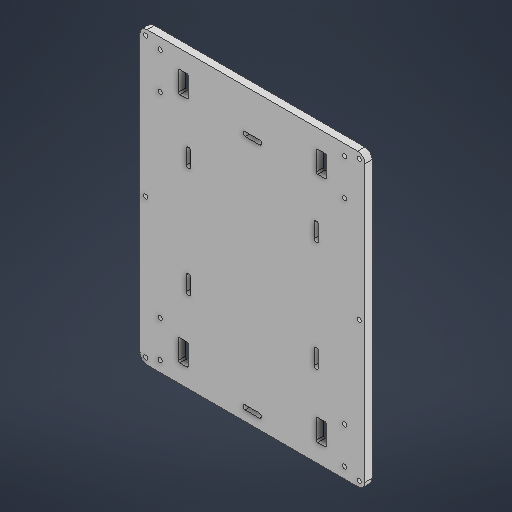
# Autodesk Inventor part: Part3
Saved by Autodesk Inventor 2026.3 (Build 303398000, 398)
## iProperties
Created: 2026-07-17
Part Number: Part3
Material: Generic
Document SubType Name: Modeling
Designer: nose
Density: 1 g/cm^3
Appearance: Default
motor_x_offset: 14.000 mm
motor_y_offset: 20.000 mm
base_width: 155.000 mm
base_length: 200.000 mm
standoff_offset: 4.000 mm
base_fillet: 5.000 mm
Author: nose
Autodesk Inventor part; units mm, degrees
ref_plane "YZ Plane" through (0, 0, 0) normal (1, 0, 0) x (0, 1, 0)
ref_plane "XZ Plane" through (0, 0, 0) normal (0, 1, 0) x (-1, 0, 0)
ref_plane "XY Plane" through (0, 0, 0) normal (0, 0, 1) x (1, 0, 0)
sketch "Sketch1" plane through (0, 0, 0) normal (0, 0, 1) x (1, 0, 0)
  line L0 (72.5, -100) -> (-72.5, -100)
  line L1 (-77.5, -95) -> (-77.5, 95)
  line L2 (-72.5, 100) -> (72.5, 100)
  line L3 (77.5, 95) -> (77.5, -95)
  line L4 (77.5, -100) -> (-77.5, 100) construction
  line L5 (-77.5, -100) -> (77.5, 100) construction
  arc A0 (-72.5, 100) -> (-77.5, 95) centre (-72.5, 95) ccw
  arc A1 (77.5, 95) -> (72.5, 100) centre (72.5, 95) ccw
  arc A2 (72.5, -100) -> (77.5, -95) centre (72.5, -95) ccw
  arc A3 (-77.5, -95) -> (-72.5, -100) centre (-72.5, -95) ccw
  point P0 (0, 0)
  dimension "d0" = 155
  dimension "d1" = 200
  dimension "d26" = 5
  constraints: 12 end point, 8 point on circle, 8 point on line, 8 tangent, 4 centre point, 3 equal radius, 2 midpoint, 2 parallel, 1 horizontal, 1 perpendicular
  measures "d0" distance of L4.end L5.end
  measures "d1" distance of L5.start L4.end
  measures "d26" radius of A0
extrude "base" add sketch "Sketch1" along normal blind 5
sketch "Sketch2" plane through (0, 0, 5) normal (0, 0, 1) x (1, 0, 0)
  circle A0 centre (-63.5, 92.6) radius 1.5
  circle A1 centre (-63.5, 67.4) radius 1.5
  line L0 (-90.3018, 80) -> (-26.5899, 80) construction
  line L1 (-63.5, 59.4965) -> (-63.5, 108.4491) construction
  line L2 (-45, 72.5) -> (-50, 72.5)
  line L3 (-51, 73.5) -> (-51, 86.5)
  line L4 (-50, 87.5) -> (-45, 87.5)
  line L5 (-44, 86.5) -> (-44, 73.5)
  line L6 (-44, 72.5) -> (-51, 87.5) construction
  line L7 (-51, 72.5) -> (-44, 87.5) construction
  arc A2 (-50, 87.5) -> (-51, 86.5) centre (-50, 86.5) ccw
  arc A3 (-44, 86.5) -> (-45, 87.5) centre (-45, 86.5) ccw
  arc A4 (-45, 72.5) -> (-44, 73.5) centre (-45, 73.5) ccw
  arc A5 (-51, 73.5) -> (-50, 72.5) centre (-50, 73.5) ccw
  line L8 (0, -165.9432) -> (0, 165.9432) construction
  line L9 (-120.5021, 0) -> (120.5021, 0) construction
  circle A6 centre (63.5, 92.6) radius 1.5
  circle A7 centre (63.5, 67.4) radius 1.5
  line L10 (45, 72.5) -> (50, 72.5)
  line L11 (51, 73.5) -> (51, 86.5)
  line L12 (50, 87.5) -> (45, 87.5)
  line L13 (44, 86.5) -> (44, 73.5)
  line L14 (44, 72.5) -> (51, 87.5) construction
  line L15 (51, 72.5) -> (44, 87.5) construction
  arc A8 (51, 86.5) -> (50, 87.5) centre (50, 86.5) ccw
  arc A9 (45, 87.5) -> (44, 86.5) centre (45, 86.5) ccw
  arc A10 (44, 73.5) -> (45, 72.5) centre (45, 73.5) ccw
  arc A11 (50, 72.5) -> (51, 73.5) centre (50, 73.5) ccw
  circle A12 centre (-63.5, -92.6) radius 1.5
  circle A13 centre (-63.5, -67.4) radius 1.5
  line L16 (-45, -72.5) -> (-50, -72.5)
  line L17 (-51, -73.5) -> (-51, -86.5)
  line L18 (-50, -87.5) -> (-45, -87.5)
  line L19 (-44, -86.5) -> (-44, -73.5)
  line L20 (-44, -72.5) -> (-51, -87.5) construction
  line L21 (-51, -72.5) -> (-44, -87.5) construction
  arc A14 (-51, -86.5) -> (-50, -87.5) centre (-50, -86.5) ccw
  arc A15 (-45, -87.5) -> (-44, -86.5) centre (-45, -86.5) ccw
  arc A16 (-44, -73.5) -> (-45, -72.5) centre (-45, -73.5) ccw
  arc A17 (-50, -72.5) -> (-51, -73.5) centre (-50, -73.5) ccw
  arc A18 (51, -73.5) -> (50, -72.5) centre (50, -73.5) ccw
  line L22 (45, -72.5) -> (50, -72.5)
  line L23 (51, -73.5) -> (51, -86.5)
  arc A19 (50, -87.5) -> (51, -86.5) centre (50, -86.5) ccw
  line L24 (44, -86.5) -> (44, -73.5)
  line L25 (50, -87.5) -> (45, -87.5)
  line L26 (51, -72.5) -> (44, -87.5) construction
  line L27 (44, -72.5) -> (51, -87.5) construction
  arc A20 (44, -86.5) -> (45, -87.5) centre (45, -86.5) ccw
  arc A21 (45, -72.5) -> (44, -73.5) centre (45, -73.5) ccw
  circle A22 centre (63.5, -67.4) radius 1.5
  circle A23 centre (63.5, -92.6) radius 1.5
  point P0 (0, 0)
  point P1 (-47.5, 80)
  point P2 (-47.5, 72.5)
  point P3 (63.5, 59.4965)
  point P4 (47.5, 80)
  point P5 (47.5, 72.5)
  point P6 (-26.5899, -80)
  point P7 (-47.5, -80)
  point P8 (-47.5, -72.5)
  point P9 (47.5, -72.5)
  point P10 (47.5, -80)
  dimension "d4" = 3
  dimension "d5" = 3
  dimension "d6" = 25.2
  dimension "d7" = 12.6
  dimension "d8" = 63.5
  dimension "d9" = 80
  dimension "d10" = 7
  dimension "d11" = 15
  dimension "d12" = 12.5
  dimension "d13" = 1
  dimension "d14" = 1
  dimension "d15" = 1
  dimension "d16" = 1
  constraints: 62 symmetric about line, 56 end point, 35 point on line, 32 point on circle, 24 centre point, 8 tangent, 5 midpoint, 3 horizontal, 2 parallel, 2 vertical, 1 perpendicular, 18 other
  measures "d4" diameter of A0
  measures "d5" diameter of A1
  measures "d6" distance of A1.centre A0.centre
  measures "d7" distance from line of L0 A0.centre
  measures "d8" distance from line of point (0, 0) L1
  measures "d9" distance from line of point (0, 0) L0
  measures "d10" distance of L6.end L7.end
  measures "d11" distance from line of point (-47.5, 72.5) L4
  measures "d12" distance from line of L3 A0.centre
  measures "d13" radius of A2
  measures "d14" radius of A3
  measures "d15" radius of A4
  measures "d16" radius of A5
extrude "motor_mount" cut sketch "Sketch2" against normal through all
sketch "Sketch4" plane through (0, 0, 5) normal (0, 0, 1) x (1, 0, 0)
  circle A0 centre (-73.5, 96) radius 1.5
  line L0 (0, -163.8328) -> (0, 163.8328) construction
  line L1 (-154.6878, 0) -> (154.6878, 0) construction
  circle A1 centre (73.5, 96) radius 1.5
  circle A2 centre (-73.5, -96) radius 1.5
  circle A3 centre (73.5, -96) radius 1.5
  circle A4 centre (-73.5, 0) radius 1.5
  line L2 (-77.5, 95) -> (-77.5, -95) projected
  circle A5 centre (73.5, 0) radius 1.5
  point P0 (0, 0)
  dimension "d21" = 3
  dimension "d22" = 73.5
  dimension "d23" = 96
  dimension "d46" = 3
  dimension "d47" = 4
  constraints: 6 centre point, 4 end point, 4 symmetric about line, 2 midpoint, 1 horizontal, 1 point on line, 1 vertical, 4 other
  measures "d21" diameter of A0
  measures "d22" horizontal distance of point (0, 0) A0.centre
  measures "d23" vertical distance of point (0, 0) A0.centre
  measures "d46" diameter of A4
  measures "d47" distance from line of L2 A4.centre
extrude "standoff_mount" cut sketch "Sketch4" against normal through all
sketch "Sketch5" plane through (0, 0, 5) normal (0, 0, 1) x (1, 0, 0)
  line L0 (-42.5, 70) -> (42.5, 70) construction
  line L1 (42.5, 70) -> (42.5, -90) construction
  line L2 (42.5, -90) -> (-42.5, -90) construction
  line L3 (-42.5, -90) -> (-42.5, 70) construction
  line L4 (-44, -58.2465) -> (-44, 58.2465) construction
  line L5 (-44, 42.7663) -> (-44, 32.7663) construction
  line L6 (-45.5, 42.7663) -> (-45.5, 32.7663)
  line L7 (-42.5, 32.7663) -> (-42.5, 42.7663)
  arc A0 (-42.5, 42.7663) -> (-45.5, 42.7663) centre (-44, 42.7663) ccw
  arc A1 (-45.5, 32.7663) -> (-42.5, 32.7663) centre (-44, 32.7663) ccw
  line L8 (0, -177.0777) -> (0, 177.0777) construction
  line L9 (-133.1759, 0) -> (133.1759, 0) construction
  line L10 (44, 42.7663) -> (44, 32.7663) construction
  line L11 (45.5, 42.7663) -> (45.5, 32.7663)
  line L12 (42.5, 32.7663) -> (42.5, 42.7663)
  arc A2 (45.5, 42.7663) -> (42.5, 42.7663) centre (44, 42.7663) ccw
  arc A3 (42.5, 32.7663) -> (45.5, 32.7663) centre (44, 32.7663) ccw
  line L13 (-44, -42.7663) -> (-44, -32.7663) construction
  line L14 (-45.5, -42.7663) -> (-45.5, -32.7663)
  line L15 (-42.5, -32.7663) -> (-42.5, -42.7663)
  arc A4 (-45.5, -42.7663) -> (-42.5, -42.7663) centre (-44, -42.7663) ccw
  arc A5 (-42.5, -32.7663) -> (-45.5, -32.7663) centre (-44, -32.7663) ccw
  arc A6 (45.5, -32.7663) -> (42.5, -32.7663) centre (44, -32.7663) ccw
  line L16 (42.5, -32.7663) -> (42.5, -42.7663)
  line L17 (44, -42.7663) -> (44, -32.7663) construction
  line L18 (45.5, -42.7663) -> (45.5, -32.7663)
  arc A7 (42.5, -42.7663) -> (45.5, -42.7663) centre (44, -42.7663) ccw
  line L19 (-82.421, 71.5) -> (90.579, 71.5) construction
  line L20 (-5, 71.5) -> (5, 71.5) construction
  line L21 (-5, 70) -> (5, 70)
  line L22 (5, 73) -> (-5, 73)
  arc A8 (-5, 73) -> (-5, 70) centre (-5, 71.5) ccw
  arc A9 (5, 70) -> (5, 73) centre (5, 71.5) ccw
  line L23 (-5, -91.5) -> (5, -91.5) construction
  line L24 (-5, -93) -> (5, -93)
  line L25 (5, -90) -> (-5, -90)
  arc A10 (-5, -90) -> (-5, -93) centre (-5, -91.5) ccw
  arc A11 (5, -93) -> (5, -90) centre (5, -91.5) ccw
  point P0 (0, 0)
  point P1 (-44, 37.7663)
  point P2 (44, 37.7663)
  point P3 (-44, -37.7663)
  point P4 (44, -37.7663)
  point P5 (0, 71.5)
  point P6 (0, -91.5)
  dimension "d27" = 85
  dimension "d28" = 160
  dimension "d29" = 42.5
  dimension "d30" = 70
  dimension "d31" = 1.5
  dimension "d32" = 10
  dimension "d33" = 3
  dimension "d34" = 1.5
  dimension "d35" = 5
  dimension "d36" = 3
  dimension "d39" = 163
  constraints: 64 end point, 24 point on circle, 21 symmetric about line, 12 centre point, 8 tangent, 5 parallel, 5 point on line, 4 midpoint, 3 horizontal, 2 vertical, 1 perpendicular, 18 other
  measures "d27" distance of L1.end L2.end
  measures "d28" distance of L0.end L1.end
  measures "d29" distance from line of point (0, 0) L3
  measures "d30" distance from line of point (0, 0) L0
  measures "d31" distance between parallel lines of L3 L4
  measures "d32" distance of L5.start L5.end
  measures "d33" diameter of A1
  measures "d34" distance between parallel lines of L0 L19
  measures "d35" distance of point (0, 71.5) L20.end
  measures "d36" diameter of A9
  measures "d39" distance of L21.start L24.start
extrude "powerbank_slot" cut sketch "Sketch5" against normal through all
equation "\"d0\" = base_width"
equation "\"d1\" = base_length"
equation "\"d26\" = base_fillet"
equation "\"d8\" = 0.5 * base_width - motor_x_offset"
equation "\"d9\" = 0.5 * base_length - motor_y_offset"
equation "\"d22\" = 0.5 * base_width - standoff_offset"
equation "\"d23\" = 0.5 * base_length - standoff_offset"
equation "\"d47\" = standoff_offset"
equation "\"motor_x_offset\" = 14"
equation "\"motor_y_offset\" = 20"
equation "\"base_width\" = 155"
equation "\"base_length\" = 200"
equation "\"standoff_offset\" = 4"
equation "\"base_fillet\" = 5"
body "Solid1"
